Autodesk Fusion 360 part; units mm, degrees
(part 2 of 2)
sketch "Sketch5 (10)" plane through (0, 0, 0) normal (0, 0, 1) x (1, 0, 0) in component "Cover"
  line L0 (-2.5, 11.9) -> (2.5, 11.9)
  line L1 (2.5, 11.9) -> (2.5, 12.7)
  line L2 (2.5, 12.7) -> (-2.5, 12.7)
  line L3 (-2.5, 12.7) -> (-2.5, 11.9)
extrude "Extrude5'''''''''" add sketch "Sketch5 (10)" along normal blind 6.1 from surface at 12.3 bodies 18 in component "Cover"
sketch "Sketch6 (10)" plane through (0, 0, 0) normal (0, 0, 1) x (1, 0, 0) in component "Cover"
  line L0 (-2, 11.3) -> (2, 11.3)
  line L1 (2, 11.3) -> (2, 11.9)
  line L2 (2, 11.9) -> (-2, 11.9)
  line L3 (-2, 11.9) -> (-2, 11.3)
extrude "Extrude6'''''''''" add sketch "Sketch6 (10)" along normal blind 0.8 from surface at 13.4 bodies 18 in component "Cover"
sketch "Sketch7 (10)" plane through (0, 0, 0) normal (0, 0, 1) x (1, 0, 0) in component "Cover"
  line L0 (-9.5, -3) -> (-8.9, -3)
  line L1 (-8.9, -3) -> (-8.9, 3)
  line L2 (-8.9, 3) -> (-9.5, 3)
  line L3 (-9.5, 3) -> (-9.5, -3)
extrude "Extrude7'''''''''" add sketch "Sketch7 (10)" along normal blind 8.5 from surface at 9.9 bodies 18 in component "Cover"
sketch "Sketch8 (10)" plane through (0, 0, 0) normal (0, 0, 1) x (1, 0, 0) in component "Cover"
  line L0 (-8.7, -4) -> (-8.2, -4)
  line L1 (-8.2, -4) -> (-8.2, 4)
  line L2 (-8.2, 4) -> (-8.7, 4)
  line L3 (-8.7, 4) -> (-8.7, -4)
extrude "Extrude8'''''''''" add sketch "Sketch8 (10)" along normal blind 4.4 from surface at 14 bodies 18 in component "Cover"
sketch "Sketch9 (6)" plane through (0, 0, 0) normal (0, 0, 1) x (1, 0, 0) in component "Cover"
  line L0 (12.2, -4) -> (12.6, -4)
  line L1 (12.6, -4) -> (12.6, 4)
  line L2 (12.6, 4) -> (12.2, 4)
  line L3 (12.2, 4) -> (12.2, -4)
extrude "Extrude9'''''" add sketch "Sketch9 (6)" along normal blind 4.4 from surface at 14 bodies 18 in component "Cover"
sketch "Sketch1 (19)" plane through (0, 0, 0) normal (0, 0, 1) x (1, 0, 0) in component "Battery_Tray"
  line L0 (-15.4, -11.6) -> (16.6, -11.6)
  line L1 (16.6, -11.6) -> (16.6, 11.6)
  line L2 (16.6, 11.6) -> (-15.4, 11.6)
  line L3 (-15.4, 11.6) -> (-15.4, -11.6)
extrude "Extrude1''''''''''''''''''" add sketch "Sketch1 (19)" along normal blind 1 from surface at -9.7 separate body makes body 19 in component "Battery_Tray"
sketch "Sketch2 (19)" plane through (0, 0, 0) normal (0, 0, 1) x (1, 0, 0) in component "Battery_Tray"
  line L0 (-11, -6) -> (11, -6)
  line L1 (11, -6) -> (11, 6)
  line L2 (11, 6) -> (-11, 6)
  line L3 (-11, 6) -> (-11, -6)
extrude "Extrude2''''''''''''''''''" cut sketch "Sketch2 (19)" along normal blind 1.2 from surface at -9.8 bodies 19 in component "Battery_Tray"
sketch "Sketch3 (15)" plane through (0, 0, 0) normal (0, 0, 1) x (1, 0, 0) in component "Battery_Tray"
  line L0 (-15.4, -11.6) -> (16.6, -11.6)
  line L1 (16.6, -11.6) -> (16.6, -10.4)
  line L2 (16.6, -10.4) -> (-15.4, -10.4)
  line L3 (-15.4, -10.4) -> (-15.4, -11.6)
extrude "Extrude3''''''''''''''" add sketch "Sketch3 (15)" along normal blind 9.7 from surface at -9.7 bodies 19 in component "Battery_Tray"
sketch "Sketch4 (11)" plane through (0, 0, 0) normal (0, 0, 1) x (1, 0, 0) in component "Battery_Tray"
  line L0 (-15.4, 10.4) -> (16.6, 10.4)
  line L1 (16.6, 10.4) -> (16.6, 11.6)
  line L2 (16.6, 11.6) -> (-15.4, 11.6)
  line L3 (-15.4, 11.6) -> (-15.4, 10.4)
extrude "Extrude4''''''''''" add sketch "Sketch4 (11)" along normal blind 9.7 from surface at -9.7 bodies 19 in component "Battery_Tray"
sketch "Sketch5 (11)" plane through (0, 0, 0) normal (0, 0, 1) x (1, 0, 0) in component "Battery_Tray"
  line L0 (15.4, -11.6) -> (16.6, -11.6)
  line L1 (16.6, -11.6) -> (16.6, 11.6)
  line L2 (16.6, 11.6) -> (15.4, 11.6)
  line L3 (15.4, 11.6) -> (15.4, -11.6)
extrude "Extrude5''''''''''" add sketch "Sketch5 (11)" along normal blind 9.7 from surface at -9.7 bodies 19 in component "Battery_Tray"
sketch "Sketch6 (11)" plane through (0, 0, 0) normal (0, 0, 1) x (1, 0, 0) in component "Battery_Tray"
  line L0 (-7.6, -14.8) -> (-4.4, -14.8)
  line L1 (-4.4, -14.8) -> (-4.4, -10.4)
  line L2 (-4.4, -10.4) -> (-7.6, -10.4)
  line L3 (-7.6, -10.4) -> (-7.6, -14.8)
extrude "Extrude6''''''''''" add sketch "Sketch6 (11)" along normal blind 1.2 from surface at -1.2 bodies 19 in component "Battery_Tray"
sketch "Sketch7 (11)" plane through (0, 0, 0) normal (0, 0, 1) x (1, 0, 0) in component "Battery_Tray"
  circle A0 centre (-6, -13.4) radius 1
extrude "Extrude7''''''''''" add sketch "Sketch7 (11)" along normal blind 2.7 from surface at -0.1 bodies 19 in component "Battery_Tray"
sketch "Sketch8 (11)" plane through (0, 0, 0) normal (0, 0, 1) x (1, 0, 0) in component "Battery_Tray"
  circle A0 centre (-6, -13.4) radius 1.5
extrude "Extrude8''''''''''" add sketch "Sketch8 (11)" along normal blind 0.6 from surface at 2 bodies 19 in component "Battery_Tray"
sketch "Sketch9 (7)" plane through (0, 0, 0) normal (0, 0, 1) x (1, 0, 0) in component "Battery_Tray"
  line L0 (-6.25, -15.2) -> (-5.75, -15.2)
  line L1 (-5.75, -15.2) -> (-5.75, -11.6)
  line L2 (-5.75, -11.6) -> (-6.25, -11.6)
  line L3 (-6.25, -11.6) -> (-6.25, -15.2)
extrude "Extrude9''''''" cut sketch "Sketch9 (7)" along normal blind 2.5 from surface at 0.2 bodies 19 in component "Battery_Tray"
sketch "Sketch10 (6)" plane through (0, 0, 0) normal (0, 0, 1) x (1, 0, 0) in component "Battery_Tray"
  line L0 (-7.6, 10.4) -> (-4.4, 10.4)
  line L1 (-4.4, 10.4) -> (-4.4, 14.8)
  line L2 (-4.4, 14.8) -> (-7.6, 14.8)
  line L3 (-7.6, 14.8) -> (-7.6, 10.4)
extrude "Extrude10'''''" add sketch "Sketch10 (6)" along normal blind 1.2 from surface at -1.2 bodies 19 in component "Battery_Tray"
sketch "Sketch11 (6)" plane through (0, 0, 0) normal (0, 0, 1) x (1, 0, 0) in component "Battery_Tray"
  circle A0 centre (-6, 13.4) radius 1
extrude "Extrude11'''''" add sketch "Sketch11 (6)" along normal blind 2.7 from surface at -0.1 bodies 19 in component "Battery_Tray"
sketch "Sketch12 (6)" plane through (0, 0, 0) normal (0, 0, 1) x (1, 0, 0) in component "Battery_Tray"
  circle A0 centre (-6, 13.4) radius 1.5
extrude "Extrude12'''''" add sketch "Sketch12 (6)" along normal blind 0.6 from surface at 2 bodies 19 in component "Battery_Tray"
sketch "Sketch13 (2)" plane through (0, 0, 0) normal (0, 0, 1) x (1, 0, 0) in component "Battery_Tray"
  line L0 (-6.25, 11.6) -> (-5.75, 11.6)
  line L1 (-5.75, 11.6) -> (-5.75, 15.2)
  line L2 (-5.75, 15.2) -> (-6.25, 15.2)
  line L3 (-6.25, 15.2) -> (-6.25, 11.6)
extrude "Extrude13'" cut sketch "Sketch13 (2)" along normal blind 2.5 from surface at 0.2 bodies 19 in component "Battery_Tray"
sketch "Sketch14 (2)" plane through (0, 0, 0) normal (0, 0, 1) x (1, 0, 0) in component "Battery_Tray"
  line L0 (4.4, -14.8) -> (7.6, -14.8)
  line L1 (7.6, -14.8) -> (7.6, -10.4)
  line L2 (7.6, -10.4) -> (4.4, -10.4)
  line L3 (4.4, -10.4) -> (4.4, -14.8)
extrude "Extrude14'" add sketch "Sketch14 (2)" along normal blind 1.2 from surface at -1.2 bodies 19 in component "Battery_Tray"
sketch "Sketch15 (2)" plane through (0, 0, 0) normal (0, 0, 1) x (1, 0, 0) in component "Battery_Tray"
  circle A0 centre (6, -13.4) radius 1
extrude "Extrude15'" add sketch "Sketch15 (2)" along normal blind 2.7 from surface at -0.1 bodies 19 in component "Battery_Tray"
sketch "Sketch16 (2)" plane through (0, 0, 0) normal (0, 0, 1) x (1, 0, 0) in component "Battery_Tray"
  circle A0 centre (6, -13.4) radius 1.5
extrude "Extrude16'" add sketch "Sketch16 (2)" along normal blind 0.6 from surface at 2 bodies 19 in component "Battery_Tray"
sketch "Sketch17 (2)" plane through (0, 0, 0) normal (0, 0, 1) x (1, 0, 0) in component "Battery_Tray"
  line L0 (5.75, -15.2) -> (6.25, -15.2)
  line L1 (6.25, -15.2) -> (6.25, -11.6)
  line L2 (6.25, -11.6) -> (5.75, -11.6)
  line L3 (5.75, -11.6) -> (5.75, -15.2)
extrude "Extrude17'" cut sketch "Sketch17 (2)" along normal blind 2.5 from surface at 0.2 bodies 19 in component "Battery_Tray"
sketch "Sketch18 (2)" plane through (0, 0, 0) normal (0, 0, 1) x (1, 0, 0) in component "Battery_Tray"
  line L0 (4.4, 10.4) -> (7.6, 10.4)
  line L1 (7.6, 10.4) -> (7.6, 14.8)
  line L2 (7.6, 14.8) -> (4.4, 14.8)
  line L3 (4.4, 14.8) -> (4.4, 10.4)
extrude "Extrude18'" add sketch "Sketch18 (2)" along normal blind 1.2 from surface at -1.2 bodies 19 in component "Battery_Tray"
sketch "Sketch19 (2)" plane through (0, 0, 0) normal (0, 0, 1) x (1, 0, 0) in component "Battery_Tray"
  circle A0 centre (6, 13.4) radius 1
extrude "Extrude19'" add sketch "Sketch19 (2)" along normal blind 2.7 from surface at -0.1 bodies 19 in component "Battery_Tray"
sketch "Sketch20 (2)" plane through (0, 0, 0) normal (0, 0, 1) x (1, 0, 0) in component "Battery_Tray"
  circle A0 centre (6, 13.4) radius 1.5
extrude "Extrude20'" add sketch "Sketch20 (2)" along normal blind 0.6 from surface at 2 bodies 19 in component "Battery_Tray"
sketch "Sketch21 (2)" plane through (0, 0, 0) normal (0, 0, 1) x (1, 0, 0) in component "Battery_Tray"
  line L0 (5.75, 11.6) -> (6.25, 11.6)
  line L1 (6.25, 11.6) -> (6.25, 15.2)
  line L2 (6.25, 15.2) -> (5.75, 15.2)
  line L3 (5.75, 15.2) -> (5.75, 11.6)
extrude "Extrude21'" cut sketch "Sketch21 (2)" along normal blind 2.5 from surface at 0.2 bodies 19 in component "Battery_Tray"
sketch "Sketch22 (2)" plane through (0, 0, 0) normal (0, 0, 1) x (1, 0, 0) in component "Battery_Tray"
  line L0 (-12, -11.7) -> (-10.4, -11.7)
  line L1 (-10.4, -11.7) -> (-10.4, -11.2)
  line L2 (-10.4, -11.2) -> (-12, -11.2)
  line L3 (-12, -11.2) -> (-12, -11.7)
extrude "Extrude22'" cut sketch "Sketch22 (2)" along normal blind 1.6 from surface at -6 bodies 19 in component "Battery_Tray"
sketch "Sketch23 (2)" plane through (0, 0, 0) normal (0, 0, 1) x (1, 0, 0) in component "Battery_Tray"
  line L0 (-12, 11.2) -> (-10.4, 11.2)
  line L1 (-10.4, 11.2) -> (-10.4, 11.7)
  line L2 (-10.4, 11.7) -> (-12, 11.7)
  line L3 (-12, 11.7) -> (-12, 11.2)
extrude "Extrude23'" cut sketch "Sketch23 (2)" along normal blind 1.6 from surface at -6 bodies 19 in component "Battery_Tray"
sketch "Sketch1 (20)" plane through (0, 0, 0) normal (0, 0, 1) x (1, 0, 0) in component "Battery_Latch"
  line L0 (-16.6, -12.6) -> (-15.4, -12.6)
  line L1 (-15.4, -12.6) -> (-15.4, 12.6)
  line L2 (-15.4, 12.6) -> (-16.6, 12.6)
  line L3 (-16.6, 12.6) -> (-16.6, -12.6)
extrude "Extrude1'''''''''''''''''''" add sketch "Sketch1 (20)" along normal blind 8.9 from surface at -9.7 separate body makes body 20 in component "Battery_Latch"
sketch "Sketch2 (20)" plane through (0, 0, 0) normal (0, 0, 1) x (1, 0, 0) in component "Battery_Latch"
  line L0 (-17, -3.5) -> (-15, -3.5)
  line L1 (-15, -3.5) -> (-15, 3.5)
  line L2 (-15, 3.5) -> (-17, 3.5)
  line L3 (-17, 3.5) -> (-17, -3.5)
extrude "Extrude2'''''''''''''''''''" cut sketch "Sketch2 (20)" along normal blind 5 from surface at -7.2 bodies 20 in component "Battery_Latch"
sketch "Sketch3 (16)" plane through (0, 0, 0) normal (0, 0, 1) x (1, 0, 0) in component "Battery_Latch"
  line L0 (-16.6, -12.6) -> (-9.4, -12.6)
  line L1 (-9.4, -12.6) -> (-9.4, -11.8)
  line L2 (-9.4, -11.8) -> (-16.6, -11.8)
  line L3 (-16.6, -11.8) -> (-16.6, -12.6)
extrude "Extrude3'''''''''''''''" add sketch "Sketch3 (16)" along normal blind 7.5 from surface at -9 bodies 20 in component "Battery_Latch"
sketch "Sketch4 (12)" plane through (0, 0, 0) normal (0, 0, 1) x (1, 0, 0) in component "Battery_Latch"
  line L0 (-11.7, -11.9) -> (-10.7, -11.9)
  line L1 (-10.7, -11.9) -> (-10.7, -11.3)
  line L2 (-10.7, -11.3) -> (-11.7, -11.3)
  line L3 (-11.7, -11.3) -> (-11.7, -11.9)
extrude "Extrude4'''''''''''" add sketch "Sketch4 (12)" along normal blind 1 from surface at -5.7 bodies 20 in component "Battery_Latch"
sketch "Sketch5 (12)" plane through (0, 0, 0) normal (0, 0, 1) x (1, 0, 0) in component "Battery_Latch"
  line L0 (-16.6, 11.8) -> (-9.4, 11.8)
  line L1 (-9.4, 11.8) -> (-9.4, 12.6)
  line L2 (-9.4, 12.6) -> (-16.6, 12.6)
  line L3 (-16.6, 12.6) -> (-16.6, 11.8)
extrude "Extrude5'''''''''''" add sketch "Sketch5 (12)" along normal blind 7.5 from surface at -9 bodies 20 in component "Battery_Latch"
sketch "Sketch6 (12)" plane through (0, 0, 0) normal (0, 0, 1) x (1, 0, 0) in component "Battery_Latch"
  line L0 (-11.7, 11.3) -> (-10.7, 11.3)
  line L1 (-10.7, 11.3) -> (-10.7, 11.9)
  line L2 (-10.7, 11.9) -> (-11.7, 11.9)
  line L3 (-11.7, 11.9) -> (-11.7, 11.3)
extrude "Extrude6'''''''''''" add sketch "Sketch6 (12)" along normal blind 1 from surface at -5.7 bodies 20 in component "Battery_Latch"
sketch "Sketch1 (21)" plane through (0, 0, 0) normal (0, 0, 1) x (1, 0, 0) in component "FitTest_Coupon"
  line L0 (-30, -67) -> (30, -67)
  line L1 (30, -67) -> (30, -53)
  line L2 (30, -53) -> (-30, -53)
  line L3 (-30, -53) -> (-30, -67)
extrude "Extrude1''''''''''''''''''''" add sketch "Sketch1 (21)" along normal blind 5 separate body makes body 21 in component "FitTest_Coupon"
sketch "Sketch2 (21)" plane through (0, 0, 0) normal (0, 0, 1) x (1, 0, 0) in component "FitTest_Coupon"
  circle A0 centre (-22.5, -60) radius 3.6
extrude "Extrude2''''''''''''''''''''" cut sketch "Sketch2 (21)" along normal blind 5.2 from surface at -0.1 bodies 21 in component "FitTest_Coupon"
sketch "Sketch3 (17)" plane through (0, 0, 0) normal (0, 0, 1) x (1, 0, 0) in component "FitTest_Coupon"
  circle A0 centre (-7.5, -60) radius 3.65
extrude "Extrude3''''''''''''''''" cut sketch "Sketch3 (17)" along normal blind 5.2 from surface at -0.1 bodies 21 in component "FitTest_Coupon"
sketch "Sketch4 (13)" plane through (0, 0, 0) normal (0, 0, 1) x (1, 0, 0) in component "FitTest_Coupon"
  circle A0 centre (7.5, -60) radius 3.7
extrude "Extrude4''''''''''''" cut sketch "Sketch4 (13)" along normal blind 5.2 from surface at -0.1 bodies 21 in component "FitTest_Coupon"
sketch "Sketch5 (13)" plane through (0, 0, 0) normal (0, 0, 1) x (1, 0, 0) in component "FitTest_Coupon"
  circle A0 centre (22.5, -60) radius 3.75
extrude "Extrude5''''''''''''" cut sketch "Sketch5 (13)" along normal blind 5.2 from surface at -0.1 bodies 21 in component "FitTest_Coupon"
sketch "Sketch1 (22)" plane through (0, 0, 0) normal (0, 0, 1) x (1, 0, 0) in component "XIAO_ESP32S3"
  line L0 (-8.6, -8.9) -> (12.4, -8.9)
  line L1 (12.4, -8.9) -> (12.4, 8.9)
  line L2 (12.4, 8.9) -> (-8.6, 8.9)
  line L3 (-8.6, 8.9) -> (-8.6, -8.9)
extrude "Extrude1'''''''''''''''''''''" add sketch "Sketch1 (22)" along normal blind 1.2 from surface at 10 separate body makes body 22 in component "XIAO_ESP32S3"
sketch "Sketch2 (22)" plane through (0, 0, 0) normal (0, 0, 1) x (1, 0, 0) in component "XIAO_ESP32S3"
  line L0 (-7.6, -6.5) -> (6.4, -6.5)
  line L1 (6.4, -6.5) -> (6.4, 6.5)
  line L2 (6.4, 6.5) -> (-7.6, 6.5)
  line L3 (-7.6, 6.5) -> (-7.6, -6.5)
extrude "Extrude2'''''''''''''''''''''" add sketch "Sketch2 (22)" along normal blind 2.4 from surface at 11.1 bodies 22 in component "XIAO_ESP32S3"
sketch "Sketch3 (18)" plane through (0, 0, 0) normal (0, 0, 1) x (1, 0, 0) in component "XIAO_ESP32S3"
  line L0 (7.9, -4.6) -> (13.1, -4.6)
  line L1 (13.1, -4.6) -> (13.1, 4.6)
  line L2 (13.1, 4.6) -> (7.9, 4.6)
  line L3 (7.9, 4.6) -> (7.9, -4.6)
extrude "Extrude3'''''''''''''''''" add sketch "Sketch3 (18)" along normal blind 3.2 from surface at 10.3 bodies 22 in component "XIAO_ESP32S3"
sketch "Sketch1 (23)" plane through (0, 0, 0) normal (0, 0, 1) x (1, 0, 0) in component "MPU6050_GY521"
  line L0 (-8, -8) -> (12, -8)
  line L1 (12, -8) -> (12, 8)
  line L2 (12, 8) -> (-8, 8)
  line L3 (-8, 8) -> (-8, -8)
extrude "Extrude1''''''''''''''''''''''" add sketch "Sketch1 (23)" along normal blind 1.6 from surface at 14.5 separate body makes body 23 in component "MPU6050_GY521"
sketch "Sketch2 (23)" plane through (0, 0, 0) normal (0, 0, 1) x (1, 0, 0) in component "MPU6050_GY521"
  circle A0 centre (-5.5, 0) radius 1.5
extrude "Extrude2''''''''''''''''''''''" cut sketch "Sketch2 (23)" along normal blind 1.8 from surface at 14.4 bodies 23 in component "MPU6050_GY521"
sketch "Sketch3 (19)" plane through (0, 0, 0) normal (0, 0, 1) x (1, 0, 0) in component "MPU6050_GY521"
  line L0 (-2.5, -5.5) -> (9.5, -5.5)
  line L1 (9.5, -5.5) -> (9.5, 5.5)
  line L2 (9.5, 5.5) -> (-2.5, 5.5)
  line L3 (-2.5, 5.5) -> (-2.5, -5.5)
extrude "Extrude3''''''''''''''''''" add sketch "Sketch3 (19)" along normal blind 1.5 from surface at 16 bodies 23 in component "MPU6050_GY521"
sketch "Sketch1 (24)" plane through (0, 0, 0) normal (0, 0, 1) x (1, 0, 0) in component "Custom_Driver_PCB"
  line L0 (-12.5, -9) -> (12.5, -9)
  line L1 (12.5, -9) -> (12.5, 9)
  line L2 (12.5, 9) -> (-12.5, 9)
  line L3 (-12.5, 9) -> (-12.5, -9)
extrude "Extrude1'''''''''''''''''''''''" add sketch "Sketch1 (24)" along normal blind 1.6 from surface at 3.2 separate body makes body 24 in component "Custom_Driver_PCB"
sketch "Sketch2 (24)" plane through (0, 0, 0) normal (0, 0, 1) x (1, 0, 0) in component "Custom_Driver_PCB"
  circle A0 centre (-10, -7) radius 1.05
extrude "Extrude2'''''''''''''''''''''''" cut sketch "Sketch2 (24)" along normal blind 1.8 from surface at 3.1 bodies 24 in component "Custom_Driver_PCB"
sketch "Sketch3 (20)" plane through (0, 0, 0) normal (0, 0, 1) x (1, 0, 0) in component "Custom_Driver_PCB"
  circle A0 centre (-10, 7) radius 1.05
extrude "Extrude3'''''''''''''''''''" cut sketch "Sketch3 (20)" along normal blind 1.8 from surface at 3.1 bodies 24 in component "Custom_Driver_PCB"
sketch "Sketch4 (14)" plane through (0, 0, 0) normal (0, 0, 1) x (1, 0, 0) in component "Custom_Driver_PCB"
  circle A0 centre (10, -7) radius 1.05
extrude "Extrude4'''''''''''''" cut sketch "Sketch4 (14)" along normal blind 1.8 from surface at 3.1 bodies 24 in component "Custom_Driver_PCB"
sketch "Sketch5 (14)" plane through (0, 0, 0) normal (0, 0, 1) x (1, 0, 0) in component "Custom_Driver_PCB"
  circle A0 centre (10, 7) radius 1.05
extrude "Extrude5'''''''''''''" cut sketch "Sketch5 (14)" along normal blind 1.8 from surface at 3.1 bodies 24 in component "Custom_Driver_PCB"
sketch "Sketch6 (13)" plane through (0, 0, 0) normal (0, 0, 1) x (1, 0, 0) in component "Custom_Driver_PCB"
  line L0 (-8.6, -5.8) -> (8.6, -5.8)
  line L1 (8.6, -5.8) -> (8.6, 5.8)
  line L2 (8.6, 5.8) -> (-8.6, 5.8)
  line L3 (-8.6, 5.8) -> (-8.6, -5.8)
extrude "Extrude6''''''''''''" add sketch "Sketch6 (13)" along normal blind 4.3 from surface at 4.7 bodies 24 in component "Custom_Driver_PCB"
sketch "Sketch1 (25)" plane through (0, 0, 0) normal (0, 0, 1) x (1, 0, 0) in component "Battery_1S_500mAh"
  line L0 (-15, -10) -> (15, -10)
  line L1 (15, -10) -> (15, 10)
  line L2 (15, 10) -> (-15, 10)
  line L3 (-15, 10) -> (-15, -10)
extrude "Extrude1''''''''''''''''''''''''" add sketch "Sketch1 (25)" along normal blind 8 from surface at -8.4 separate body makes body 25 in component "Battery_1S_500mAh"
sketch "Sketch2 (25)" plane through (0, 0, 0) normal (0, 0, 1) x (1, 0, 0) in component "Battery_1S_500mAh"
  line L0 (-27, -1.5) -> (-14.9, -1.5)
  line L1 (-14.9, -1.5) -> (-14.9, 1.5)
  line L2 (-14.9, 1.5) -> (-27, 1.5)
  line L3 (-27, 1.5) -> (-27, -1.5)
extrude "Extrude2''''''''''''''''''''''''" add sketch "Sketch2 (25)" along normal blind 1.5 from surface at -5.15 bodies 25 in component "Battery_1S_500mAh"
sketch "Sketch3 (21)" plane through (0, 0, 0) normal (0, 0, 1) x (1, 0, 0) in component "Battery_1S_500mAh"
  line L0 (-27, -2.25) -> (-20.5, -2.25)
  line L1 (-20.5, -2.25) -> (-20.5, 2.25)
  line L2 (-20.5, 2.25) -> (-27, 2.25)
  line L3 (-27, 2.25) -> (-27, -2.25)
extrude "Extrude3''''''''''''''''''''" add sketch "Sketch3 (21)" along normal blind 4.3 from surface at -6.55 bodies 25 in component "Battery_1S_500mAh"
component "Frame_Core" placed x (1, 0, 0) y (0, 1, 0) z (0, 0, 1) at (0, 0, 0)
component "Arm_FR" placed x (1, 0, 0) y (0, 1, 0) z (0, 0, 1) at (0, 0, 0)
component "Pod_FR" placed x (1, 0, 0) y (0, 1, 0) z (0, 0, 1) at (0, 0, 0)
component "Motor_FR" placed x (1, 0, 0) y (0, 1, 0) z (0, 0, 1) at (0, 0, 0)
component "Prop_FR" placed x (1, 0, 0) y (0, 1, 0) z (0, 0, 1) at (0, 0, 0)
component "Arm_FL" placed x (1, 0, 0) y (0, 1, 0) z (0, 0, 1) at (0, 0, 0)
component "Pod_FL" placed x (1, 0, 0) y (0, 1, 0) z (0, 0, 1) at (0, 0, 0)
component "Motor_FL" placed x (1, 0, 0) y (0, 1, 0) z (0, 0, 1) at (0, 0, 0)
component "Prop_FL" placed x (1, 0, 0) y (0, 1, 0) z (0, 0, 1) at (0, 0, 0)
component "Arm_RL" placed x (1, 0, 0) y (0, 1, 0) z (0, 0, 1) at (0, 0, 0)
component "Pod_RL" placed x (1, 0, 0) y (0, 1, 0) z (0, 0, 1) at (0, 0, 0)
component "Motor_RL" placed x (1, 0, 0) y (0, 1, 0) z (0, 0, 1) at (0, 0, 0)
component "Prop_RL" placed x (1, 0, 0) y (0, 1, 0) z (0, 0, 1) at (0, 0, 0)
component "Arm_RR" placed x (1, 0, 0) y (0, 1, 0) z (0, 0, 1) at (0, 0, 0)
component "Pod_RR" placed x (1, 0, 0) y (0, 1, 0) z (0, 0, 1) at (0, 0, 0)
component "Motor_RR" placed x (1, 0, 0) y (0, 1, 0) z (0, 0, 1) at (0, 0, 0)
component "Prop_RR" placed x (1, 0, 0) y (0, 1, 0) z (0, 0, 1) at (0, 0, 0)
component "Cover" placed x (1, 0, 0) y (0, 1, 0) z (0, 0, 1) at (0, 0, 0)
component "Battery_Tray" placed x (1, 0, 0) y (0, 1, 0) z (0, 0, 1) at (0, 0, 0)
component "Battery_Latch" placed x (1, 0, 0) y (0, 1, 0) z (0, 0, 1) at (0, 0, 0)
component "FitTest_Coupon" placed x (1, 0, 0) y (0, 1, 0) z (0, 0, 1) at (0, 0, 0)
component "XIAO_ESP32S3" placed x (1, 0, 0) y (0, 1, 0) z (0, 0, 1) at (0, 0, 0)
component "MPU6050_GY521" placed x (1, 0, 0) y (0, 1, 0) z (0, 0, 1) at (0, 0, 0)
component "Custom_Driver_PCB" placed x (1, 0, 0) y (0, 1, 0) z (0, 0, 1) at (0, 0, 0)
component "Battery_1S_500mAh" placed x (1, 0, 0) y (0, 1, 0) z (0, 0, 1) at (0, 0, 0)
equation "diag_mm = 60.0 mm" comment "mirror of P dict (edit script to change)"
equation "prop_d_mm = 40.0 mm" comment "mirror of P dict (edit script to change)"
equation "motor_clear_mm = 0.15 mm" comment "mirror of P dict (edit script to change)"
equation "plate_t_mm = 2.0 mm" comment "mirror of P dict (edit script to change)"
named bodies: "Frame_Core", "Arm_FR", "Pod_FR", "Motor_FR", "Prop_FR", "Arm_FL", "Pod_FL", "Motor_FL", "Prop_FL", "Arm_RL", "Pod_RL", "Motor_RL", "Prop_RL", "Arm_RR", "Pod_RR", "Motor_RR", "Prop_RR", "Cover", "Battery_Tray", "Battery_Latch", "FitTest_Coupon", "XIAO_ESP32S3", "MPU6050_GY521", "Custom_Driver_PCB", "Battery_1S_500mAh"
